Autodesk Fusion 360 part; units mm, degrees
(part 6 of 6)
  spline S31 degree 5 poles (-9.8759, -5.4427) (-9.8816, -5.4458) (-9.8931, -5.452) (-9.9106, -5.4607) (-9.9345, -5.4713) (-9.9649, -5.4833) (-9.9958, -5.4944) (-10.027, -5.5049) (-10.0584, -5.515) (-10.0899, -5.525) (-10.1215, -5.5347) (-10.1532, -5.5441) (-10.1851, -5.5532) (-10.2172, -5.5617) (-10.2496, -5.5698) (-10.2821, -5.5775) (-10.3148, -5.5848) (-10.3476, -5.5917) (-10.3806, -5.5984) (-10.4137, -5.6049) (-10.4468, -5.611) (-10.4801, -5.6169) (-10.5135, -5.6225) (-10.5471, -5.6278) (-10.5807, -5.6328) (-10.6145, -5.6375) (-10.6484, -5.642) (-10.6823, -5.6461) (-10.7164, -5.6501) (-10.7506, -5.6537) (-10.7848, -5.6571) (-10.8192, -5.6603) (-10.8536, -5.6633) (-10.8881, -5.6659) (-10.9227, -5.6684) (-10.9574, -5.6706) (-10.9922, -5.6725) (-11.027, -5.6742) (-11.062, -5.6757) (-11.097, -5.677) (-11.132, -5.678) (-11.1672, -5.6788) (-11.2024, -5.6794) (-11.2377, -5.6797) (-11.273, -5.6799) (-11.3084, -5.6798) (-11.3439, -5.6795) (-11.3795, -5.6789) (-11.4151, -5.6782) (-11.4507, -5.6772) (-11.4864, -5.6761) (-11.5222, -5.6747) (-11.558, -5.6731) (-11.5939, -5.6713) (-11.6299, -5.6693) (-11.6659, -5.6671) (-11.7019, -5.6646) (-11.738, -5.662) (-11.7741, -5.6591) (-11.8103, -5.6561) (-11.8465, -5.6529) (-11.8828, -5.6494) (-11.9191, -5.6457) (-11.9555, -5.6419) (-11.9919, -5.6378) (-12.0283, -5.6336) (-12.0648, -5.6291) (-12.1013, -5.6245) (-12.1379, -5.6197) (-12.1745, -5.6146) (-12.2111, -5.6094) (-12.2405, -5.605) (-12.2625, -5.6017) (-12.2772, -5.5994) (-12.2845, -5.5983) knots 0 0 0 0 0 0 0.01428571 0.02857143 0.04285714 0.05714286 0.07142857 0.08571429 0.1 0.11428571 0.12857143 0.14285714 0.15714286 0.17142857 0.18571429 0.2 0.21428571 0.22857143 0.24285714 0.25714286 0.27142857 0.28571429 0.3 0.31428571 0.32857143 0.34285714 0.35714286 0.37142857 0.38571429 0.4 0.41428571 0.42857143 0.44285714 0.45714286 0.47142857 0.48571429 0.5 0.51428571 0.52857143 0.54285714 0.55714286 0.57142857 0.58571429 0.6 0.61428571 0.62857143 0.64285714 0.65714286 0.67142857 0.68571429 0.7 0.71428571 0.72857143 0.74285714 0.75714286 0.77142857 0.78571429 0.8 0.81428571 0.82857143 0.84285714 0.85714286 0.87142857 0.88571429 0.9 0.91428571 0.92857143 0.94285714 0.95714286 0.97142857 0.98571429 1 1 1 1 1 1
  line L31 (-9.8759, -5.4427) -> (-9.4174, -5.19)
  arc A63 (-8.7499, -5.3665) -> (-9.4174, -5.19) centre (-9.1761, -5.6279) ccw
  arc A64 (-8.7499, -5.3665) -> (-8.3065, -6.0302) centre (0, 0) ccw
  line L32 (0, -13.5) -> (0, -13.53)
  circle A65 centre (0, 0) radius 1.25
  dimension "d18" = 2.5
  constraint midpoint A10 L32.start
  constraint perpendicular A10 L32
  constraint coincident A0.centre A2.centre
  measures "d18" diameter of A65
extrude "押し出し6" cut sketch "スケッチ7" against normal blind 200 contours A65
named bodies: "Spur Gear (16 teeth)"
